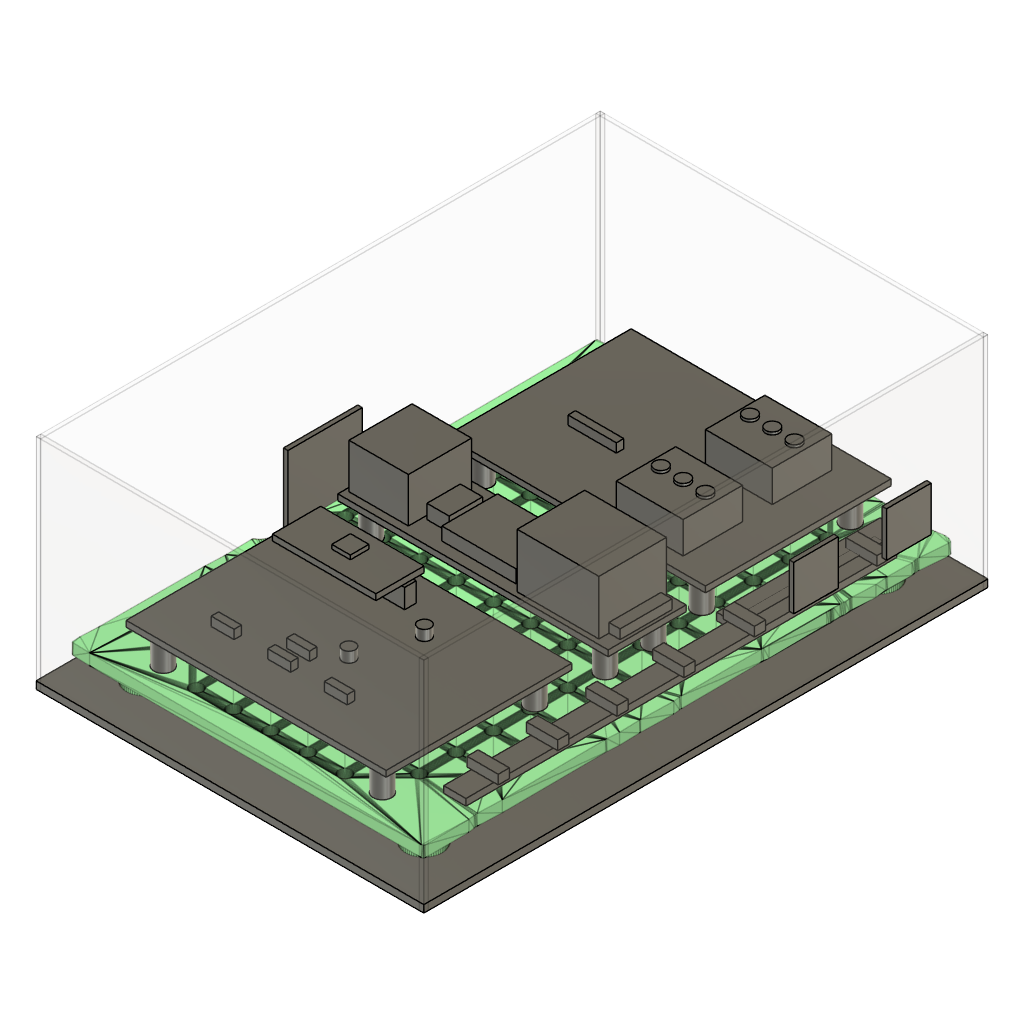
R2_PROVISIONAL_Assembly_NATIVE (Autodesk Fusion 360 design; units mm, degrees)
part number: 2026-11-12-01-49-28-463
part number: 2026-11-12-01-49-28-809
part number: 2026-11-12-01-49-28-966
part number: 2026-11-12-01-49-29-130
part number: 2026-11-12-01-49-29-156
part number: 2026-11-12-01-49-29-376
part number: 2026-11-12-01-49-29-409
part number: 2026-11-12-01-49-29-438
part number: 2026-11-12-01-49-29-469
part number: 2026-11-12-01-49-29-503
part number: 2026-11-12-01-49-29-543
part number: 2026-11-12-01-49-29-590
part number: 2026-11-12-01-49-29-623
part number: 2026-11-12-01-49-29-659
part number: 2026-11-12-01-49-29-706
part number: 2026-11-12-01-49-29-748
part number: 2026-11-12-01-49-29-789
part number: 2026-11-12-01-49-29-835
part number: 2026-11-12-01-49-29-884
part number: 2026-11-12-01-49-29-933
part number: 2026-11-12-01-49-29-988
part number: 2026-11-12-01-49-30-037
part number: 2026-11-12-01-49-30-170
part number: 2026-11-12-01-49-30-217
part number: 2026-11-12-01-49-30-343
part number: 2026-11-12-01-49-30-395
part number: 2026-11-12-01-49-30-925
part number: 2026-11-12-01-49-31-045
part number: 2026-11-12-01-49-31-113
part number: 2026-11-12-01-49-31-183
part number: 2026-11-12-01-49-31-255
part number: 2026-11-12-01-49-31-332
part number: 2026-11-12-01-49-31-399
part number: 2026-11-12-01-49-31-468
part number: 2026-11-12-01-49-31-541
part number: 2026-11-12-01-49-31-562
part number: 2026-11-12-01-49-31-635
part number: 2026-11-12-01-49-31-719
part number: 2026-11-12-01-49-31-797
Autodesk Fusion 360 part; units mm, degrees
sketch "Provisional case floor from exterior paper trace profile" plane through (0, 0, 0) normal (0, 0, 1) x (1, 0, 0) in component "01 | PROVISIONAL original enclosure exterior trace 104.4x151.9"
  line L0 (-4.62, -4.624) -> (99.78, -4.624)
  line L1 (99.78, -4.624) -> (99.78, 147.276)
  line L2 (99.78, 147.276) -> (-4.62, 147.276)
  line L3 (-4.62, 147.276) -> (-4.62, -4.624)
extrude "Extrude1" add sketch "Provisional case floor from exterior paper trace profile" along normal blind 2 makes body 1 in component "01 | PROVISIONAL original enclosure exterior trace 104.4x151.9"
sketch "left enclosure wall profile" plane through (0, 0, 0) normal (0, 0, 1) x (1, 0, 0) in component "01 | PROVISIONAL original enclosure exterior trace 104.4x151.9"
  line L0 (-4.62, -4.624) -> (-3.42, -4.624)
  line L1 (-3.42, -4.624) -> (-3.42, 147.276)
  line L2 (-3.42, 147.276) -> (-4.62, 147.276)
  line L3 (-4.62, 147.276) -> (-4.62, -4.624)
extrude "Extrude2" add sketch "left enclosure wall profile" along normal blind 59 separate body makes body 2 in component "01 | PROVISIONAL original enclosure exterior trace 104.4x151.9"
sketch "right enclosure wall profile" plane through (0, 0, 0) normal (0, 0, 1) x (1, 0, 0) in component "01 | PROVISIONAL original enclosure exterior trace 104.4x151.9"
  line L0 (98.58, -4.624) -> (99.78, -4.624)
  line L1 (99.78, -4.624) -> (99.78, 147.276)
  line L2 (99.78, 147.276) -> (98.58, 147.276)
  line L3 (98.58, 147.276) -> (98.58, -4.624)
extrude "Extrude3" add sketch "right enclosure wall profile" along normal blind 59 separate body makes body 3 in component "01 | PROVISIONAL original enclosure exterior trace 104.4x151.9"
sketch "front enclosure wall profile" plane through (0, 0, 0) normal (0, 0, 1) x (1, 0, 0) in component "01 | PROVISIONAL original enclosure exterior trace 104.4x151.9"
  line L0 (-4.62, -4.624) -> (99.78, -4.624)
  line L1 (99.78, -4.624) -> (99.78, -3.424)
  line L2 (99.78, -3.424) -> (-4.62, -3.424)
  line L3 (-4.62, -3.424) -> (-4.62, -4.624)
extrude "Extrude4" add sketch "front enclosure wall profile" along normal blind 59 separate body makes body 4 in component "01 | PROVISIONAL original enclosure exterior trace 104.4x151.9"
sketch "back enclosure wall profile" plane through (0, 0, 0) normal (0, 0, 1) x (1, 0, 0) in component "01 | PROVISIONAL original enclosure exterior trace 104.4x151.9"
  line L0 (-4.62, 146.076) -> (99.78, 146.076)
  line L1 (99.78, 146.076) -> (99.78, 147.276)
  line L2 (99.78, 147.276) -> (-4.62, 147.276)
  line L3 (-4.62, 147.276) -> (-4.62, 146.076)
extrude "Extrude5" add sketch "back enclosure wall profile" along normal blind 59 separate body makes body 5 in component "01 | PROVISIONAL original enclosure exterior trace 104.4x151.9"
other "Base Mesh Feature1" in component "02 | VERIFIED P4 mesh (unchanged, feet down)"
sketch "70x50 isolated-pad perfboard A profile" plane through (0, 0, 0) normal (0, 0, 1) x (1, 0, 0) in component "03 | BOARD A detailed concept ADS1115 + R1-R4 + C1/C2"
  line L0 (0, 0) -> (70, 0)
  line L1 (70, 0) -> (70, 50)
  line L2 (70, 50) -> (0, 50)
  line L3 (0, 50) -> (0, 0)
extrude "Extrude1'" add sketch "70x50 isolated-pad perfboard A profile" along normal blind 1.6 separate body makes body 6 in component "03 | BOARD A detailed concept ADS1115 + R1-R4 + C1/C2"
sketch "10-way female breakaway socket envelope profile" plane through (0, 0, 0) normal (0, 0, 1) x (1, 0, 0) in component "ACTUAL header P3-P12 (10 pins)"
  line L0 (9.57, 39.96) -> (35.03, 39.96)
  line L1 (35.03, 39.96) -> (35.03, 43.06)
  line L2 (35.03, 43.06) -> (9.57, 43.06)
  line L3 (9.57, 43.06) -> (9.57, 39.96)
extrude "Extrude1''" add sketch "10-way female breakaway socket envelope profile" along normal blind 5.2 separate body makes body 7 in component "ACTUAL header P3-P12 (10 pins)"
sketch "Header pin P3 circle" plane through (0, 0, 0) normal (0, 0, 1) x (1, 0, 0) in component "ACTUAL header P3-P12 (10 pins)"
  circle A0 centre (10.87, 41.51) radius 0.55
extrude "Extrude2'" add sketch "Header pin P3 circle" along normal blind 6.1 separate body makes body 8 in component "ACTUAL header P3-P12 (10 pins)"
sketch "Header pin P4 circle" plane through (0, 0, 0) normal (0, 0, 1) x (1, 0, 0) in component "ACTUAL header P3-P12 (10 pins)"
  circle A0 centre (13.41, 41.51) radius 0.55
extrude "Extrude3'" add sketch "Header pin P4 circle" along normal blind 6.1 separate body makes body 9 in component "ACTUAL header P3-P12 (10 pins)"
sketch "Header pin P5 circle" plane through (0, 0, 0) normal (0, 0, 1) x (1, 0, 0) in component "ACTUAL header P3-P12 (10 pins)"
  circle A0 centre (15.95, 41.51) radius 0.55
extrude "Extrude4'" add sketch "Header pin P5 circle" along normal blind 6.1 separate body makes body 10 in component "ACTUAL header P3-P12 (10 pins)"
sketch "Header pin P6 circle" plane through (0, 0, 0) normal (0, 0, 1) x (1, 0, 0) in component "ACTUAL header P3-P12 (10 pins)"
  circle A0 centre (18.49, 41.51) radius 0.55
extrude "Extrude5'" add sketch "Header pin P6 circle" along normal blind 6.1 separate body makes body 11 in component "ACTUAL header P3-P12 (10 pins)"
sketch "Header pin P7 circle" plane through (0, 0, 0) normal (0, 0, 1) x (1, 0, 0) in component "ACTUAL header P3-P12 (10 pins)"
  circle A0 centre (21.03, 41.51) radius 0.55
extrude "Extrude6" add sketch "Header pin P7 circle" along normal blind 6.1 separate body makes body 12 in component "ACTUAL header P3-P12 (10 pins)"
sketch "Header pin P8 circle" plane through (0, 0, 0) normal (0, 0, 1) x (1, 0, 0) in component "ACTUAL header P3-P12 (10 pins)"
  circle A0 centre (23.57, 41.51) radius 0.55
extrude "Extrude7" add sketch "Header pin P8 circle" along normal blind 6.1 separate body makes body 13 in component "ACTUAL header P3-P12 (10 pins)"
sketch "Header pin P9 circle" plane through (0, 0, 0) normal (0, 0, 1) x (1, 0, 0) in component "ACTUAL header P3-P12 (10 pins)"
  circle A0 centre (26.11, 41.51) radius 0.55
extrude "Extrude8" add sketch "Header pin P9 circle" along normal blind 6.1 separate body makes body 14 in component "ACTUAL header P3-P12 (10 pins)"
sketch "Header pin P10 circle" plane through (0, 0, 0) normal (0, 0, 1) x (1, 0, 0) in component "ACTUAL header P3-P12 (10 pins)"
  circle A0 centre (28.65, 41.51) radius 0.55
extrude "Extrude9" add sketch "Header pin P10 circle" along normal blind 6.1 separate body makes body 15 in component "ACTUAL header P3-P12 (10 pins)"
sketch "Header pin P11 circle" plane through (0, 0, 0) normal (0, 0, 1) x (1, 0, 0) in component "ACTUAL header P3-P12 (10 pins)"
  circle A0 centre (31.19, 41.51) radius 0.55
extrude "Extrude10" add sketch "Header pin P11 circle" along normal blind 6.1 separate body makes body 16 in component "ACTUAL header P3-P12 (10 pins)"
sketch "Header pin P12 circle" plane through (0, 0, 0) normal (0, 0, 1) x (1, 0, 0) in component "ACTUAL header P3-P12 (10 pins)"
  circle A0 centre (33.73, 41.51) radius 0.55
extrude "Extrude11" add sketch "Header pin P12 circle" along normal blind 6.1 separate body makes body 17 in component "ACTUAL header P3-P12 (10 pins)"
sketch "ADS1115 10-pin blue PCB mock profile" plane through (0, 0, 0) normal (0, 0, 1) x (1, 0, 0) in component "Removable ADS1115 breakout blue placeholder (10 pins)"
  line L0 (8.37, 31.01) -> (36.23, 31.01)
  line L1 (36.23, 31.01) -> (36.23, 44.01)
  line L2 (36.23, 44.01) -> (8.37, 44.01)
  line L3 (8.37, 44.01) -> (8.37, 31.01)
extrude "Extrude1'''" add sketch "ADS1115 10-pin blue PCB mock profile" along normal blind 1.6 separate body makes body 18 in component "Removable ADS1115 breakout blue placeholder (10 pins)"
sketch "ADS1115 chip mock profile" plane through (0, 0, 0) normal (0, 0, 1) x (1, 0, 0) in component "ADC silicon IC body"
  line L0 (19.87, 35.51) -> (24.87, 35.51)
  line L1 (24.87, 35.51) -> (24.87, 40.51)
  line L2 (24.87, 40.51) -> (19.87, 40.51)
  line L3 (19.87, 40.51) -> (19.87, 35.51)
extrude "Extrude1''''" add sketch "ADS1115 chip mock profile" along normal blind 1.1 separate body makes body 19 in component "ADC silicon IC body"
sketch "R1 10k resistor body profile" plane through (0, 0, 0) normal (0, 0, 1) x (1, 0, 0) in component "R1 10k (preexisting soldered)"
  line L0 (12.87, 10.03) -> (19.03, 10.03)
  line L1 (19.03, 10.03) -> (19.03, 12.03)
  line L2 (19.03, 12.03) -> (12.87, 12.03)
  line L3 (12.87, 12.03) -> (12.87, 10.03)
extrude "Extrude1'''''" add sketch "R1 10k resistor body profile" along normal blind 2.4 separate body makes body 20 in component "R1 10k (preexisting soldered)"
sketch "R2 10k resistor body profile" plane through (0, 0, 0) normal (0, 0, 1) x (1, 0, 0) in component "R2 10k (preexisting soldered)"
  line L0 (28.11, 10.03) -> (34.27, 10.03)
  line L1 (34.27, 10.03) -> (34.27, 12.03)
  line L2 (34.27, 12.03) -> (28.11, 12.03)
  line L3 (28.11, 12.03) -> (28.11, 10.03)
extrude "Extrude1''''''" add sketch "R2 10k resistor body profile" along normal blind 2.4 separate body makes body 21 in component "R2 10k (preexisting soldered)"
sketch "R3 4.7k resistor body profile" plane through (0, 0, 0) normal (0, 0, 1) x (1, 0, 0) in component "R3 4.7k (preexisting soldered)"
  line L0 (43.35, 10.03) -> (49.51, 10.03)
  line L1 (49.51, 10.03) -> (49.51, 12.03)
  line L2 (49.51, 12.03) -> (43.35, 12.03)
  line L3 (43.35, 12.03) -> (43.35, 10.03)
extrude "Extrude1'''''''" add sketch "R3 4.7k resistor body profile" along normal blind 2.4 separate body makes body 22 in component "R3 4.7k (preexisting soldered)"
sketch "R4 1k resistor body profile" plane through (0, 0, 0) normal (0, 0, 1) x (1, 0, 0) in component "R4 1k (preexisting soldered)"
  line L0 (28.11, 15.11) -> (34.27, 15.11)
  line L1 (34.27, 15.11) -> (34.27, 17.11)
  line L2 (34.27, 17.11) -> (28.11, 17.11)
  line L3 (28.11, 17.11) -> (28.11, 15.11)
extrude "Extrude1''''''''" add sketch "R4 1k resistor body profile" along normal blind 2.4 separate body makes body 23 in component "R4 1k (preexisting soldered)"
sketch "C1 100nF 104 disk marker circle" plane through (0, 0, 0) normal (0, 0, 1) x (1, 0, 0) in component "C1 100nF 104 (preexisting soldered)"
  circle A0 centre (38.81, 21.19) radius 1.7
extrude "Extrude1'''''''''" add sketch "C1 100nF 104 disk marker circle" along normal blind 2.8 separate body makes body 24 in component "C1 100nF 104 (preexisting soldered)"
sketch "C2 100nF 104 disk marker circle" plane through (0, 0, 0) normal (0, 0, 1) x (1, 0, 0) in component "C2 100nF 104 (preexisting soldered)"
  circle A0 centre (43.89, 36.43) radius 1.7
extrude "Extrude1''''''''''" add sketch "C2 100nF 104 disk marker circle" along normal blind 2.8 separate body makes body 25 in component "C2 100nF 104 (preexisting soldered)"
sketch "Waveshare board 72.8x21 reference profile" plane through (0, 0, 0) normal (0, 0, 1) x (1, 0, 0) in component "04 | Waveshare ESP32-S3-ETH/PoE (controller separate)"
  line L0 (0, 0) -> (72.8, 0)
  line L1 (72.8, 0) -> (72.8, 21)
  line L2 (72.8, 21) -> (0, 21)
  line L3 (0, 21) -> (0, 0)
extrude "Extrude1'''''''''''" add sketch "Waveshare board 72.8x21 reference profile" along normal blind 1.6 separate body makes body 26 in component "04 | Waveshare ESP32-S3-ETH/PoE (controller separate)"
sketch "RJ45 connector housing (illustrative) profile" plane through (0, 0, 0) normal (0, 0, 1) x (1, 0, 0) in component "Factory RJ45 Ethernet jack + plug clearance envelope"
  line L0 (1, 2) -> (17, 2)
  line L1 (17, 2) -> (17, 19)
  line L2 (17, 19) -> (1, 19)
  line L3 (1, 19) -> (1, 2)
extrude "Extrude1''''''''''''" add sketch "RJ45 connector housing (illustrative) profile" along normal blind 12 separate body makes body 27 in component "Factory RJ45 Ethernet jack + plug clearance envelope"
sketch "RF shield can profile" plane through (0, 0, 0) normal (0, 0, 1) x (1, 0, 0) in component "ESP32-S3 RF shield"
  line L0 (25, 3) -> (45, 3)
  line L1 (45, 3) -> (45, 18)
  line L2 (45, 18) -> (25, 18)
  line L3 (25, 18) -> (25, 3)
extrude "Extrude1'''''''''''''" add sketch "RF shield can profile" along normal blind 3.5 separate body makes body 28 in component "ESP32-S3 RF shield"
sketch "PoE isolated converter region mock profile" plane through (0, 0, 0) normal (0, 0, 1) x (1, 0, 0) in component "Existing PoE daughterboard STACK HEIGHT ESTIMATE"
  line L0 (47, 1.3) -> (69, 1.3)
  line L1 (69, 1.3) -> (69, 19.5)
  line L2 (69, 19.5) -> (47, 19.5)
  line L3 (47, 19.5) -> (47, 1.3)
extrude "Extrude1''''''''''''''" add sketch "PoE isolated converter region mock profile" along normal blind 14.6 separate body makes body 29 in component "Existing PoE daughterboard STACK HEIGHT ESTIMATE"
sketch "USB port block profile" plane through (0, 0, 0) normal (0, 0, 1) x (1, 0, 0) in component "USB test port envelope"
  line L0 (18, 6) -> (24, 6)
  line L1 (24, 6) -> (24, 15)
  line L2 (24, 15) -> (18, 15)
  line L3 (18, 15) -> (18, 6)
extrude "Extrude1'''''''''''''''" add sketch "USB port block profile" along normal blind 3.8 separate body makes body 30 in component "USB test port envelope"
sketch "Two service buttons mock profile" plane through (0, 0, 0) normal (0, 0, 1) x (1, 0, 0) in component "BOOT RESET button group"
  line L0 (69, 4) -> (72, 4)
  line L1 (72, 4) -> (72, 18)
  line L2 (72, 18) -> (69, 18)
  line L3 (69, 18) -> (69, 4)
extrude "Extrude1''''''''''''''''" add sketch "Two service buttons mock profile" along normal blind 2.5 separate body makes body 31 in component "BOOT RESET button group"
sketch "70x50 isolated-pad perfboard B profile" plane through (0, 0, 0) normal (0, 0, 1) x (1, 0, 0) in component "05 | BOARD B J1 pressure + J2 temperature + R5"
  line L0 (0, 0) -> (70, 0)
  line L1 (70, 0) -> (70, 50)
  line L2 (70, 50) -> (0, 50)
  line L3 (0, 50) -> (0, 0)
extrude "Extrude1'''''''''''''''''" add sketch "70x50 isolated-pad perfboard B profile" along normal blind 1.6 separate body makes body 32 in component "05 | BOARD B J1 pressure + J2 temperature + R5"
sketch "J1 PRESS +5V GND SIG housing profile" plane through (0, 0, 0) normal (0, 0, 1) x (1, 0, 0) in component "J1 PRESS +5V GND SIG independent 3-position block"
  line L0 (42, 4) -> (60, 4)
  line L1 (60, 4) -> (60, 20)
  line L2 (60, 20) -> (42, 20)
  line L3 (42, 20) -> (42, 4)
extrude "Extrude1''''''''''''''''''" add sketch "J1 PRESS +5V GND SIG housing profile" along normal blind 8.5 separate body makes body 33 in component "J1 PRESS +5V GND SIG independent 3-position block"
sketch "J1 PRESS +5V GND SIG pin 1 screw circle" plane through (0, 0, 0) normal (0, 0, 1) x (1, 0, 0) in component "J1 PRESS +5V GND SIG three screw heads"
  circle A0 centre (45, 13) radius 1.8
extrude "Extrude1'''''''''''''''''''" add sketch "J1 PRESS +5V GND SIG pin 1 screw circle" along normal blind 0.7 separate body makes body 34 in component "J1 PRESS +5V GND SIG three screw heads"
sketch "J1 PRESS +5V GND SIG pin 2 screw circle" plane through (0, 0, 0) normal (0, 0, 1) x (1, 0, 0) in component "J1 PRESS +5V GND SIG three screw heads"
  circle A0 centre (51, 13) radius 1.8
extrude "Extrude2''" add sketch "J1 PRESS +5V GND SIG pin 2 screw circle" along normal blind 0.7 separate body makes body 35 in component "J1 PRESS +5V GND SIG three screw heads"
sketch "J1 PRESS +5V GND SIG pin 3 screw circle" plane through (0, 0, 0) normal (0, 0, 1) x (1, 0, 0) in component "J1 PRESS +5V GND SIG three screw heads"
  circle A0 centre (57, 13) radius 1.8
extrude "Extrude3''" add sketch "J1 PRESS +5V GND SIG pin 3 screw circle" along normal blind 0.7 separate body makes body 36 in component "J1 PRESS +5V GND SIG three screw heads"
sketch "J2 TEMP +3V3 DATA GND housing profile" plane through (0, 0, 0) normal (0, 0, 1) x (1, 0, 0) in component "J2 TEMP +3V3 DATA GND independent 3-position block"
  line L0 (42, 28) -> (60, 28)
  line L1 (60, 28) -> (60, 44)
  line L2 (60, 44) -> (42, 44)
  line L3 (42, 44) -> (42, 28)
extrude "Extrude1''''''''''''''''''''" add sketch "J2 TEMP +3V3 DATA GND housing profile" along normal blind 8.5 separate body makes body 37 in component "J2 TEMP +3V3 DATA GND independent 3-position block"
sketch "J2 TEMP +3V3 DATA GND pin 1 screw circle" plane through (0, 0, 0) normal (0, 0, 1) x (1, 0, 0) in component "J2 TEMP +3V3 DATA GND three screw heads"
  circle A0 centre (45, 37) radius 1.8
extrude "Extrude1'''''''''''''''''''''" add sketch "J2 TEMP +3V3 DATA GND pin 1 screw circle" along normal blind 0.7 separate body makes body 38 in component "J2 TEMP +3V3 DATA GND three screw heads"
sketch "J2 TEMP +3V3 DATA GND pin 2 screw circle" plane through (0, 0, 0) normal (0, 0, 1) x (1, 0, 0) in component "J2 TEMP +3V3 DATA GND three screw heads"
  circle A0 centre (51, 37) radius 1.8
extrude "Extrude2'''" add sketch "J2 TEMP +3V3 DATA GND pin 2 screw circle" along normal blind 0.7 separate body makes body 39 in component "J2 TEMP +3V3 DATA GND three screw heads"
sketch "J2 TEMP +3V3 DATA GND pin 3 screw circle" plane through (0, 0, 0) normal (0, 0, 1) x (1, 0, 0) in component "J2 TEMP +3V3 DATA GND three screw heads"
  circle A0 centre (57, 37) radius 1.8
extrude "Extrude3'''" add sketch "J2 TEMP +3V3 DATA GND pin 3 screw circle" along normal blind 0.7 separate body makes body 40 in component "J2 TEMP +3V3 DATA GND three screw heads"
sketch "R5 4.7k marker profile" plane through (0, 0, 0) normal (0, 0, 1) x (1, 0, 0) in component "R5 4.7k from J2 3V3 to DATA"
  line L0 (14, 19) -> (27, 19)
  line L1 (27, 19) -> (27, 21)
  line L2 (27, 21) -> (14, 21)
  line L3 (14, 21) -> (14, 19)
extrude "Extrude1''''''''''''''''''''''" add sketch "R5 4.7k marker profile" along normal blind 2.4 separate body makes body 41 in component "R5 4.7k from J2 3V3 to DATA"
sketch "A insulated riser 1 circle" plane through (0, 0, 0) normal (0, 0, 1) x (1, 0, 0) in component "06 | 8mm insulated supports mock - holes UNVERIFIED"
  circle A0 centre (18, 7) radius 2.5
extrude "Extrude1'''''''''''''''''''''''" add sketch "A insulated riser 1 circle" along normal blind 8 separate body makes body 42 in component "06 | 8mm insulated supports mock - holes UNVERIFIED"
sketch "A insulated riser 2 circle" plane through (0, 0, 0) normal (0, 0, 1) x (1, 0, 0) in component "06 | 8mm insulated supports mock - holes UNVERIFIED"
  circle A0 centre (77, 7) radius 2.5
extrude "Extrude2''''" add sketch "A insulated riser 2 circle" along normal blind 8 separate body makes body 43 in component "06 | 8mm insulated supports mock - holes UNVERIFIED"
sketch "A insulated riser 3 circle" plane through (0, 0, 0) normal (0, 0, 1) x (1, 0, 0) in component "06 | 8mm insulated supports mock - holes UNVERIFIED"
  circle A0 centre (18, 48) radius 2.5
extrude "Extrude3''''" add sketch "A insulated riser 3 circle" along normal blind 8 separate body makes body 44 in component "06 | 8mm insulated supports mock - holes UNVERIFIED"
sketch "A insulated riser 4 circle" plane through (0, 0, 0) normal (0, 0, 1) x (1, 0, 0) in component "06 | 8mm insulated supports mock - holes UNVERIFIED"
  circle A0 centre (77, 48) radius 2.5
extrude "Extrude4''" add sketch "A insulated riser 4 circle" along normal blind 8 separate body makes body 45 in component "06 | 8mm insulated supports mock - holes UNVERIFIED"
sketch "ESP insulated riser 1 circle" plane through (0, 0, 0) normal (0, 0, 1) x (1, 0, 0) in component "06 | 8mm insulated supports mock - holes UNVERIFIED"
  circle A0 centre (16, 65) radius 2.5
extrude "Extrude5''" add sketch "ESP insulated riser 1 circle" along normal blind 8 separate body makes body 46 in component "06 | 8mm insulated supports mock - holes UNVERIFIED"
sketch "ESP insulated riser 2 circle" plane through (0, 0, 0) normal (0, 0, 1) x (1, 0, 0) in component "06 | 8mm insulated supports mock - holes UNVERIFIED"
  circle A0 centre (79, 65) radius 2.5
extrude "Extrude6'" add sketch "ESP insulated riser 2 circle" along normal blind 8 separate body makes body 47 in component "06 | 8mm insulated supports mock - holes UNVERIFIED"
sketch "ESP insulated riser 3 circle" plane through (0, 0, 0) normal (0, 0, 1) x (1, 0, 0) in component "06 | 8mm insulated supports mock - holes UNVERIFIED"
  circle A0 centre (16, 78) radius 2.5
extrude "Extrude7'" add sketch "ESP insulated riser 3 circle" along normal blind 8 separate body makes body 48 in component "06 | 8mm insulated supports mock - holes UNVERIFIED"
sketch "ESP insulated riser 4 circle" plane through (0, 0, 0) normal (0, 0, 1) x (1, 0, 0) in component "06 | 8mm insulated supports mock - holes UNVERIFIED"
  circle A0 centre (79, 78) radius 2.5
extrude "Extrude8'" add sketch "ESP insulated riser 4 circle" along normal blind 8 separate body makes body 49 in component "06 | 8mm insulated supports mock - holes UNVERIFIED"
sketch "B insulated riser 1 circle" plane through (0, 0, 0) normal (0, 0, 1) x (1, 0, 0) in component "06 | 8mm insulated supports mock - holes UNVERIFIED"
  circle A0 centre (18, 93) radius 2.5
extrude "Extrude9'" add sketch "B insulated riser 1 circle" along normal blind 8 separate body makes body 50 in component "06 | 8mm insulated supports mock - holes UNVERIFIED"
sketch "B insulated riser 2 circle" plane through (0, 0, 0) normal (0, 0, 1) x (1, 0, 0) in component "06 | 8mm insulated supports mock - holes UNVERIFIED"
  circle A0 centre (77, 93) radius 2.5
extrude "Extrude10'" add sketch "B insulated riser 2 circle" along normal blind 8 separate body makes body 51 in component "06 | 8mm insulated supports mock - holes UNVERIFIED"
sketch "B insulated riser 3 circle" plane through (0, 0, 0) normal (0, 0, 1) x (1, 0, 0) in component "06 | 8mm insulated supports mock - holes UNVERIFIED"
  circle A0 centre (18, 133) radius 2.5
extrude "Extrude11'" add sketch "B insulated riser 3 circle" along normal blind 8 separate body makes body 52 in component "06 | 8mm insulated supports mock - holes UNVERIFIED"
sketch "B insulated riser 4 circle" plane through (0, 0, 0) normal (0, 0, 1) x (1, 0, 0) in component "06 | 8mm insulated supports mock - holes UNVERIFIED"
  circle A0 centre (77, 133) radius 2.5
extrude "Extrude12" add sketch "B insulated riser 4 circle" along normal blind 8 separate body makes body 53 in component "06 | 8mm insulated supports mock - holes UNVERIFIED"
sketch "Right 6mm W07-W09 B-to-A 3-wire corridor profile" plane through (0, 0, 0) normal (0, 0, 1) x (1, 0, 0) in component "07 | Service harness guide (not actual conductors)"
  line L0 (86.5, 14) -> (92.5, 14)
  line L1 (92.5, 14) -> (92.5, 130)
  line L2 (92.5, 130) -> (86.5, 130)
  line L3 (86.5, 130) -> (86.5, 14)
extrude "Extrude1''''''''''''''''''''''''" add sketch "Right 6mm W07-W09 B-to-A 3-wire corridor profile" along normal blind 1.8 separate body makes body 54 in component "07 | Service harness guide (not actual conductors)"
sketch "Cable restraint lane to Board B profile" plane through (0, 0, 0) normal (0, 0, 1) x (1, 0, 0) in component "07 | Service harness guide (not actual conductors)"
  line L0 (83, 91) -> (89, 91)
  line L1 (89, 91) -> (89, 135)
  line L2 (89, 135) -> (83, 135)
  line L3 (83, 135) -> (83, 91)
extrude "Extrude2'''''" add sketch "Cable restraint lane to Board B profile" along normal blind 2 separate body makes body 55 in component "07 | Service harness guide (not actual conductors)"
sketch "tie saddle marker profile" plane through (0, 0, 0) normal (0, 0, 1) x (1, 0, 0) in component "removable nylon tie saddle location 1"
  line L0 (85.3, 21.5) -> (93.7, 21.5)
  line L1 (93.7, 21.5) -> (93.7, 24.5)
  line L2 (93.7, 24.5) -> (85.3, 24.5)
  line L3 (85.3, 24.5) -> (85.3, 21.5)
extrude "Extrude1'''''''''''''''''''''''''" add sketch "tie saddle marker profile" along normal blind 2.5 separate body makes body 56 in component "removable nylon tie saddle location 1"
sketch "tie saddle marker profile (2)" plane through (0, 0, 0) normal (0, 0, 1) x (1, 0, 0) in component "removable nylon tie saddle location 2"
  line L0 (85.3, 37.5) -> (93.7, 37.5)
  line L1 (93.7, 37.5) -> (93.7, 40.5)
  line L2 (93.7, 40.5) -> (85.3, 40.5)
  line L3 (85.3, 40.5) -> (85.3, 37.5)
extrude "Extrude1''''''''''''''''''''''''''" add sketch "tie saddle marker profile (2)" along normal blind 2.5 separate body makes body 57 in component "removable nylon tie saddle location 2"
sketch "tie saddle marker profile (3)" plane through (0, 0, 0) normal (0, 0, 1) x (1, 0, 0) in component "removable nylon tie saddle location 3"
  line L0 (85.3, 53.5) -> (93.7, 53.5)
  line L1 (93.7, 53.5) -> (93.7, 56.5)
  line L2 (93.7, 56.5) -> (85.3, 56.5)
  line L3 (85.3, 56.5) -> (85.3, 53.5)
extrude "Extrude1'''''''''''''''''''''''''''" add sketch "tie saddle marker profile (3)" along normal blind 2.5 separate body makes body 58 in component "removable nylon tie saddle location 3"
sketch "tie saddle marker profile (4)" plane through (0, 0, 0) normal (0, 0, 1) x (1, 0, 0) in component "removable nylon tie saddle location 4"
  line L0 (85.3, 71.5) -> (93.7, 71.5)
  line L1 (93.7, 71.5) -> (93.7, 74.5)
  line L2 (93.7, 74.5) -> (85.3, 74.5)
  line L3 (85.3, 74.5) -> (85.3, 71.5)
extrude "Extrude1''''''''''''''''''''''''''''" add sketch "tie saddle marker profile (4)" along normal blind 2.5 separate body makes body 59 in component "removable nylon tie saddle location 4"
sketch "tie saddle marker profile (5)" plane through (0, 0, 0) normal (0, 0, 1) x (1, 0, 0) in component "removable nylon tie saddle location 5"
  line L0 (85.3, 90.5) -> (93.7, 90.5)
  line L1 (93.7, 90.5) -> (93.7, 93.5)
  line L2 (93.7, 93.5) -> (85.3, 93.5)
  line L3 (85.3, 93.5) -> (85.3, 90.5)
extrude "Extrude1'''''''''''''''''''''''''''''" add sketch "tie saddle marker profile (5)" along normal blind 2.5 separate body makes body 60 in component "removable nylon tie saddle location 5"
sketch "tie saddle marker profile (6)" plane through (0, 0, 0) normal (0, 0, 1) x (1, 0, 0) in component "removable nylon tie saddle location 6"
  line L0 (85.3, 109.5) -> (93.7, 109.5)
  line L1 (93.7, 109.5) -> (93.7, 112.5)
  line L2 (93.7, 112.5) -> (85.3, 112.5)
  line L3 (85.3, 112.5) -> (85.3, 109.5)
extrude "Extrude1''''''''''''''''''''''''''''''" add sketch "tie saddle marker profile (6)" along normal blind 2.5 separate body makes body 61 in component "removable nylon tie saddle location 6"
sketch "tie saddle marker profile (7)" plane through (0, 0, 0) normal (0, 0, 1) x (1, 0, 0) in component "removable nylon tie saddle location 7"
  line L0 (85.3, 123.5) -> (93.7, 123.5)
  line L1 (93.7, 123.5) -> (93.7, 126.5)
  line L2 (93.7, 126.5) -> (85.3, 126.5)
  line L3 (85.3, 126.5) -> (85.3, 123.5)
extrude "Extrude1'''''''''''''''''''''''''''''''" add sketch "tie saddle marker profile (7)" along normal blind 2.5 separate body makes body 62 in component "removable nylon tie saddle location 7"
sketch "J1 PRESSURE right wall entry zone no-drill highlight profile" plane through (0, 0, 0) normal (0, 0, 1) x (1, 0, 0) in component "J1 PRESSURE right wall entry zone UNDRILLED"
  line L0 (98.58, 95) -> (99.78, 95)
  line L1 (99.78, 95) -> (99.78, 107)
  line L2 (99.78, 107) -> (98.58, 107)
  line L3 (98.58, 107) -> (98.58, 95)
extrude "Extrude1''''''''''''''''''''''''''''''''" add sketch "J1 PRESSURE right wall entry zone no-drill highlight profile" along normal blind 12 separate body makes body 63 in component "J1 PRESSURE right wall entry zone UNDRILLED"
sketch "J2 TEMPERATURE right wall entry zone no-drill highlight profile" plane through (0, 0, 0) normal (0, 0, 1) x (1, 0, 0) in component "J2 TEMPERATURE right wall entry zone UNDRILLED"
  line L0 (98.58, 120) -> (99.78, 120)
  line L1 (99.78, 120) -> (99.78, 132)
  line L2 (99.78, 132) -> (98.58, 132)
  line L3 (98.58, 132) -> (98.58, 120)
extrude "Extrude1'''''''''''''''''''''''''''''''''" add sketch "J2 TEMPERATURE right wall entry zone no-drill highlight profile" along normal blind 12 separate body makes body 64 in component "J2 TEMPERATURE right wall entry zone UNDRILLED"
sketch "RJ45 gland zone left wall - DO NOT DRILL profile" plane through (0, 0, 0) normal (0, 0, 1) x (1, 0, 0) in component "ETH split-gland / serviceable RJ45 ENTRY concept"
  line L0 (-4.62, 62) -> (-3.42, 62)
  line L1 (-3.42, 62) -> (-3.42, 82)
  line L2 (-3.42, 82) -> (-4.62, 82)
  line L3 (-4.62, 82) -> (-4.62, 62)
extrude "Extrude1''''''''''''''''''''''''''''''''''" add sketch "RJ45 gland zone left wall - DO NOT DRILL profile" along normal blind 23 separate body makes body 65 in component "ETH split-gland / serviceable RJ45 ENTRY concept"
sketch "Removable lid conceptual silhouette profile" plane through (0, 0, 0) normal (0, 0, 1) x (1, 0, 0) in component "09 | Existing gasket lid mock (hidden for service)"
  line L0 (-4.62, -4.624) -> (99.78, -4.624)
  line L1 (99.78, -4.624) -> (99.78, 147.276)
  line L2 (99.78, 147.276) -> (-4.62, 147.276)
  line L3 (-4.62, 147.276) -> (-4.62, -4.624)
extrude "Extrude1'''''''''''''''''''''''''''''''''''" add sketch "Removable lid conceptual silhouette profile" along normal blind 3.2 separate body makes body 66 in component "09 | Existing gasket lid mock (hidden for service)"
component "01 | PROVISIONAL original enclosure exterior trace 104.4x151.9" placed x (1, 0, 0) y (0, 1, 0) z (0, 0, 1) at (0, 0, 0)
component "02 | VERIFIED P4 mesh (unchanged, feet down)" placed x (1, 0, 0) y (0, -1, 0) z (0, 0, -1) at (0, 142.652, 11)
component "03 | BOARD A detailed concept ADS1115 + R1-R4 + C1/C2" placed x (1, 0, 0) y (0, 1, 0) z (0, 0, 1) at (12, 3, 19)
component "04 | Waveshare ESP32-S3-ETH/PoE (controller separate)" placed x (1, 0, 0) y (0, 1, 0) z (0, 0, 1) at (11, 61, 19)
component "05 | BOARD B J1 pressure + J2 temperature + R5" placed x (1, 0, 0) y (0, 1, 0) z (0, 0, 1) at (12, 89, 19)
component "06 | 8mm insulated supports mock - holes UNVERIFIED" placed x (1, 0, 0) y (0, 1, 0) z (0, 0, 1) at (0, 0, 11)
component "07 | Service harness guide (not actual conductors)" placed x (1, 0, 0) y (0, 1, 0) z (0, 0, 1) at (0, 0, 12)
component "08 | 3 cable ENTRY ZONES (no cut geometry)" placed x (1, 0, 0) y (0, 1, 0) z (0, 0, 1) at (0, 0, 0)
component "09 | Existing gasket lid mock (hidden for service)" placed x (1, 0, 0) y (0, 1, 0) z (0, 0, 1) at (0, 0, 59)
component "ACTUAL header P3-P12 (10 pins)" placed x (1, 0, 0) y (0, 1, 0) z (0, 0, 1) at (0, 0, 1.6) in component "03 | BOARD A detailed concept ADS1115 + R1-R4 + C1/C2"
component "Removable ADS1115 breakout blue placeholder (10 pins)" placed x (1, 0, 0) y (0, 1, 0) z (0, 0, 1) at (0, 0, 8.8) in component "03 | BOARD A detailed concept ADS1115 + R1-R4 + C1/C2"
component "ADC silicon IC body" placed x (1, 0, 0) y (0, 1, 0) z (0, 0, 1) at (0, 0, 10.4) in component "03 | BOARD A detailed concept ADS1115 + R1-R4 + C1/C2"
component "R1 10k (preexisting soldered)" placed x (1, 0, 0) y (0, 1, 0) z (0, 0, 1) at (0, 0, 1.6) in component "03 | BOARD A detailed concept ADS1115 + R1-R4 + C1/C2"
component "R2 10k (preexisting soldered)" placed x (1, 0, 0) y (0, 1, 0) z (0, 0, 1) at (0, 0, 1.6) in component "03 | BOARD A detailed concept ADS1115 + R1-R4 + C1/C2"
component "R3 4.7k (preexisting soldered)" placed x (1, 0, 0) y (0, 1, 0) z (0, 0, 1) at (0, 0, 1.6) in component "03 | BOARD A detailed concept ADS1115 + R1-R4 + C1/C2"
component "R4 1k (preexisting soldered)" placed x (1, 0, 0) y (0, 1, 0) z (0, 0, 1) at (0, 0, 1.6) in component "03 | BOARD A detailed concept ADS1115 + R1-R4 + C1/C2"
component "C1 100nF 104 (preexisting soldered)" placed x (1, 0, 0) y (0, 1, 0) z (0, 0, 1) at (0, 0, 1.6) in component "03 | BOARD A detailed concept ADS1115 + R1-R4 + C1/C2"
component "C2 100nF 104 (preexisting soldered)" placed x (1, 0, 0) y (0, 1, 0) z (0, 0, 1) at (0, 0, 1.6) in component "03 | BOARD A detailed concept ADS1115 + R1-R4 + C1/C2"
component "Factory RJ45 Ethernet jack + plug clearance envelope" placed x (1, 0, 0) y (0, 1, 0) z (0, 0, 1) at (0, 0, 1.6) in component "04 | Waveshare ESP32-S3-ETH/PoE (controller separate)"
component "ESP32-S3 RF shield" placed x (1, 0, 0) y (0, 1, 0) z (0, 0, 1) at (0, 0, 1.6) in component "04 | Waveshare ESP32-S3-ETH/PoE (controller separate)"
component "Existing PoE daughterboard STACK HEIGHT ESTIMATE" placed x (1, 0, 0) y (0, 1, 0) z (0, 0, 1) at (0, 0, 1.6) in component "04 | Waveshare ESP32-S3-ETH/PoE (controller separate)"
component "USB test port envelope" placed x (1, 0, 0) y (0, 1, 0) z (0, 0, 1) at (0, 0, 1.6) in component "04 | Waveshare ESP32-S3-ETH/PoE (controller separate)"
component "BOOT RESET button group" placed x (1, 0, 0) y (0, 1, 0) z (0, 0, 1) at (0, 0, 1.6) in component "04 | Waveshare ESP32-S3-ETH/PoE (controller separate)"
component "J1 PRESS +5V GND SIG independent 3-position block" placed x (1, 0, 0) y (0, 1, 0) z (0, 0, 1) at (0, 0, 1.6) in component "05 | BOARD B J1 pressure + J2 temperature + R5"
component "J1 PRESS +5V GND SIG three screw heads" placed x (1, 0, 0) y (0, 1, 0) z (0, 0, 1) at (0, 0, 10.1) in component "05 | BOARD B J1 pressure + J2 temperature + R5"
component "J2 TEMP +3V3 DATA GND independent 3-position block" placed x (1, 0, 0) y (0, 1, 0) z (0, 0, 1) at (0, 0, 1.6) in component "05 | BOARD B J1 pressure + J2 temperature + R5"
component "J2 TEMP +3V3 DATA GND three screw heads" placed x (1, 0, 0) y (0, 1, 0) z (0, 0, 1) at (0, 0, 10.1) in component "05 | BOARD B J1 pressure + J2 temperature + R5"
component "R5 4.7k from J2 3V3 to DATA" placed x (1, 0, 0) y (0, 1, 0) z (0, 0, 1) at (0, 0, 1.6) in component "05 | BOARD B J1 pressure + J2 temperature + R5"
component "01 | PROVISIONAL original enclosure exterior trace 104.4x151.9" placed x (1, 0, 0) y (0, 1, 0) z (0, 0, 1) at (0, 0, 0) in component "06 | 8mm insulated supports mock - holes UNVERIFIED"
component "removable nylon tie saddle location 1" placed x (1, 0, 0) y (0, 1, 0) z (0, 0, 1) at (0, 0, 1.8) in component "07 | Service harness guide (not actual conductors)"
component "removable nylon tie saddle location 2" placed x (1, 0, 0) y (0, 1, 0) z (0, 0, 1) at (0, 0, 1.8) in component "07 | Service harness guide (not actual conductors)"
component "removable nylon tie saddle location 3" placed x (1, 0, 0) y (0, 1, 0) z (0, 0, 1) at (0, 0, 1.8) in component "07 | Service harness guide (not actual conductors)"
component "removable nylon tie saddle location 4" placed x (1, 0, 0) y (0, 1, 0) z (0, 0, 1) at (0, 0, 1.8) in component "07 | Service harness guide (not actual conductors)"
component "removable nylon tie saddle location 5" placed x (1, 0, 0) y (0, 1, 0) z (0, 0, 1) at (0, 0, 1.8) in component "07 | Service harness guide (not actual conductors)"
component "removable nylon tie saddle location 6" placed x (1, 0, 0) y (0, 1, 0) z (0, 0, 1) at (0, 0, 1.8) in component "07 | Service harness guide (not actual conductors)"
component "removable nylon tie saddle location 7" placed x (1, 0, 0) y (0, 1, 0) z (0, 0, 1) at (0, 0, 1.8) in component "07 | Service harness guide (not actual conductors)"
component "J1 PRESSURE right wall entry zone UNDRILLED" placed x (1, 0, 0) y (0, 1, 0) z (0, 0, 1) at (0, 0, 20) in component "08 | 3 cable ENTRY ZONES (no cut geometry)"
component "J2 TEMPERATURE right wall entry zone UNDRILLED" placed x (1, 0, 0) y (0, 1, 0) z (0, 0, 1) at (0, 0, 20) in component "08 | 3 cable ENTRY ZONES (no cut geometry)"
component "ETH split-gland / serviceable RJ45 ENTRY concept" placed x (1, 0, 0) y (0, 1, 0) z (0, 0, 1) at (0, 0, 0) in component "08 | 3 cable ENTRY ZONES (no cut geometry)"
named bodies: "Provisional case floor from exterior paper trace", "left enclosure wall", "right enclosure wall", "front enclosure wall", "back enclosure wall", "70x50 isolated-pad perfboard A", "10-way female breakaway socket envelope", "Header pin P3", "Header pin P4", "Header pin P5", "Header pin P6", "Header pin P7", "Header pin P8", "Header pin P9", "Header pin P10", "Header pin P11", "Header pin P12", "ADS1115 10-pin blue PCB mock", "ADS1115 chip mock", "R1 10k resistor body", "R2 10k resistor body", "R3 4.7k resistor body", "R4 1k resistor body", "C1 100nF 104 disk marker", "C2 100nF 104 disk marker", "Waveshare board 72.8x21 reference", "RJ45 connector housing (illustrative)", "RF shield can", "PoE isolated converter region mock", "USB port block", "Two service buttons mock", "70x50 isolated-pad perfboard B", "J1 PRESS +5V GND SIG housing", "J1 PRESS +5V GND SIG pin 1 screw", "J1 PRESS +5V GND SIG pin 2 screw", "J1 PRESS +5V GND SIG pin 3 screw", "J2 TEMP +3V3 DATA GND housing", "J2 TEMP +3V3 DATA GND pin 1 screw", "J2 TEMP +3V3 DATA GND pin 2 screw", "J2 TEMP +3V3 DATA GND pin 3 screw", "R5 4.7k marker", "A insulated riser 1", "A insulated riser 2", "A insulated riser 3", "A insulated riser 4", "ESP insulated riser 1", "ESP insulated riser 2", "ESP insulated riser 3", "ESP insulated riser 4", "B insulated riser 1", "B insulated riser 2", "B insulated riser 3", "B insulated riser 4", "Right 6mm W07-W09 B-to-A 3-wire corridor", "Cable restraint lane to Board B", "tie saddle marker", "J1 PRESSURE right wall entry zone no-drill highlight", "J2 TEMPERATURE right wall entry zone no-drill highlight", "RJ45 gland zone left wall - DO NOT DRILL", "Removable lid conceptual silhouette"
